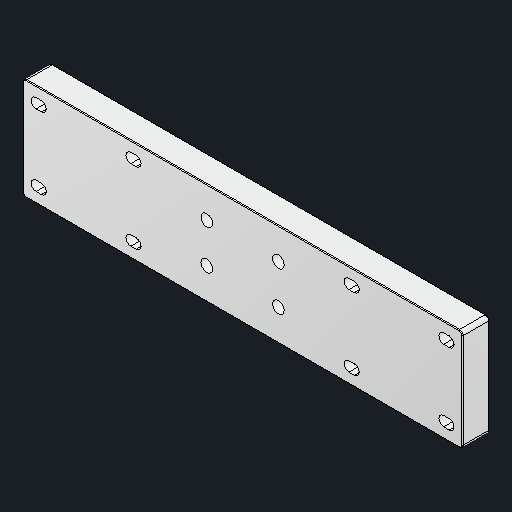
# Autodesk Inventor part: monotaro-middle-flat-carriage-plate
Saved by Autodesk Inventor 2027.1 (Build 311270010, 270A)
## iProperties
Created: 2026-11-14
Part Number: monotaro-middle-flat-carriage-plate
Material: Aluminum 6061
Document SubType Name: Modeling
Designer: queezz
Density: 2.7 g/cm^3
Appearance: Aluminum - Flat
Mass: 541.376 g
Surface Area: 402.494 cm^2
Volume: 200.51 cm^3
Author: queezz
Autodesk Inventor part; units mm, degrees
sketch "Sketch1" plane through (0, 0, 0) normal (0, 0, 1) x (1, 0, 0)
  line L0 (-123, -28.5) -> (123, -28.5)
  line L1 (123, -28.5) -> (123, 28.5)
  line L2 (123, 28.5) -> (-123, 28.5)
  line L3 (-123, 28.5) -> (-123, -28.5)
  constraints: 8 end point, 2 parallel, 1 horizontal, 1 perpendicular
extrude "Flat 15 mm aluminum bracket blank" add sketch "Sketch1" along normal blind 15
ref_plane "Work Plane1" through (0, 0, 15) normal (0, 0, 1) x (1, 0, 0)
sketch "Guide block screw layout" plane through (0, 0, 15) normal (0, 0, 1) x (1, 0, 0)
  line L0 (-115.5, -17.25) -> (-112.5, -17.25)
  line L1 (-115.5, -22.75) -> (-112.5, -22.75)
  arc A0 (-112.5, -22.75) -> (-112.5, -17.25) centre (-112.5, -20) ccw
  arc A1 (-115.5, -17.25) -> (-115.5, -22.75) centre (-115.5, -20) ccw
  line L2 (-115.5, 22.75) -> (-112.5, 22.75)
  line L3 (-115.5, 17.25) -> (-112.5, 17.25)
  arc A2 (-112.5, 17.25) -> (-112.5, 22.75) centre (-112.5, 20) ccw
  arc A3 (-115.5, 22.75) -> (-115.5, 17.25) centre (-115.5, 20) ccw
  line L4 (-62.5, -17.25) -> (-59.5, -17.25)
  line L5 (-62.5, -22.75) -> (-59.5, -22.75)
  arc A4 (-59.5, -22.75) -> (-59.5, -17.25) centre (-59.5, -20) ccw
  arc A5 (-62.5, -17.25) -> (-62.5, -22.75) centre (-62.5, -20) ccw
  line L6 (-62.5, 22.75) -> (-59.5, 22.75)
  line L7 (-62.5, 17.25) -> (-59.5, 17.25)
  arc A6 (-59.5, 17.25) -> (-59.5, 22.75) centre (-59.5, 20) ccw
  arc A7 (-62.5, 22.75) -> (-62.5, 17.25) centre (-62.5, 20) ccw
  line L8 (59.5, -17.25) -> (62.5, -17.25)
  line L9 (59.5, -22.75) -> (62.5, -22.75)
  arc A8 (62.5, -22.75) -> (62.5, -17.25) centre (62.5, -20) ccw
  arc A9 (59.5, -17.25) -> (59.5, -22.75) centre (59.5, -20) ccw
  line L10 (59.5, 22.75) -> (62.5, 22.75)
  line L11 (59.5, 17.25) -> (62.5, 17.25)
  arc A10 (62.5, 17.25) -> (62.5, 22.75) centre (62.5, 20) ccw
  arc A11 (59.5, 22.75) -> (59.5, 17.25) centre (59.5, 20) ccw
  line L12 (112.5, -17.25) -> (115.5, -17.25)
  line L13 (112.5, -22.75) -> (115.5, -22.75)
  arc A12 (115.5, -22.75) -> (115.5, -17.25) centre (115.5, -20) ccw
  arc A13 (112.5, -17.25) -> (112.5, -22.75) centre (112.5, -20) ccw
  line L14 (112.5, 22.75) -> (115.5, 22.75)
  line L15 (112.5, 17.25) -> (115.5, 17.25)
  arc A14 (115.5, 17.25) -> (115.5, 22.75) centre (115.5, 20) ccw
  arc A15 (112.5, 22.75) -> (112.5, 17.25) centre (112.5, 20) ccw
  constraints: 32 end point, 32 point on circle, 16 centre point
extrude "Eight M5 guide screw slots +-1.5" cut sketch "Guide block screw layout" against normal blind 15
ref_plane "Work Plane2" through (0, 0, 0) normal (0, 0, 1) x (1, 0, 0)
sketch "Original flange clamp hole pattern" plane through (0, 0, 0) normal (0, 0, 1) x (1, 0, 0)
  circle A0 centre (-20, -11) radius 3.3
  circle A1 centre (-20, 11) radius 3.3
  circle A2 centre (20, -11) radius 3.3
  circle A3 centre (20, 11) radius 3.3
  constraints: 4 centre point
extrude "M6 clamp screw clearances 6.6" cut sketch "Original flange clamp hole pattern" along normal blind 15
ref_plane "Work Plane3" through (0, 0, 0) normal (0, 0, 1) x (1, 0, 0)
sketch "Clamp screw head seats underside" plane through (0, 0, 0) normal (0, 0, 1) x (1, 0, 0)
  circle A0 centre (-20, -11) radius 6
  circle A1 centre (-20, 11) radius 6
  circle A2 centre (20, -11) radius 6
  circle A3 centre (20, 11) radius 6
  constraints: 4 centre point
extrude "Counterbores for M6 clamp screws" cut sketch "Clamp screw head seats underside" along normal blind 6.5
sketch "Sketch5" plane through (0, 0, 0) normal (0, 0, 1) x (1, 0, 0)
  line L0 (-32.5, 16.5) -> (32.5, 16.5)
  line L1 (32.5, 16.5) -> (32.5, 41.5)
  line L2 (32.5, 41.5) -> (-32.5, 41.5)
  line L3 (-32.5, 41.5) -> (-32.5, 16.5)
  constraints: 8 end point, 2 parallel, 1 horizontal, 1 perpendicular
extrude "Underside clearance for far screw support" [suppressed]
fillet "R2 exposed plan corners" radius 2 4 edges at (-123, -28.5, 7.5) (-123, 28.5, 7.5) (123, 28.5, 7.5) (123, -28.5, 7.5)
chamfer "C0.4 outside perimeter" distance 0.4 angle 45 16 edges at (122.4142, -27.9142, 15) (122.4142, -27.9142, 0) (123, 0, 0) (123, 0, 15) (0, -28.5, 0) (-122.4142, -27.9142, 0) (-123, 0, 0) (-122.4142, 27.9142, 0) (0, 28.5, 0) (122.4142, 27.9142, 0) (122.4142, 27.9142, 15) (0, 28.5, 15) (-122.4142, 27.9142, 15) (-123, 0, 15) (-122.4142, -27.9142, 15) (0, -28.5, 15)
body "Solid1"
